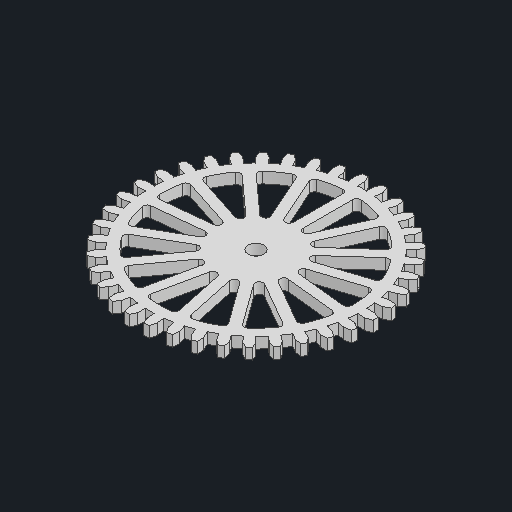
# Autodesk Inventor part: M3_38_holl_small
Saved by Autodesk Inventor 2027.1 (Build 311270010, 270A)
## iProperties
Created: 2024-04-01
Part Number: M3_38_holl_small
Material: 一般
Document SubType Name: モデリング
Designer: hibik
Density: 1 g/cm^3
Appearance: 既定
Sheet Metal Rule: Default
Author: hibik
Autodesk Inventor part; units mm, degrees
ref_plane "YZ Plane" through (0, 0, 0) normal (1, 0, 0) x (0, 1, 0)
ref_plane "XZ Plane" through (0, 0, 0) normal (0, 1, 0) x (-1, 0, 0)
ref_plane "XY Plane" through (0, 0, 0) normal (0, 0, 1) x (1, 0, 0)
sketch "スケッチ1" plane through (0, 0, 0) normal (0, 1, 0) x (-1, 0, 0)
  circle A0 centre (0, 0) radius 57 construction
  circle A1 centre (0, 0) radius 60 construction
  line L0 (60, 1.2454) -> (60, -1.2454)
  line L1 (60, 1.2454) -> (56.9513, 2.355)
  line L2 (60, -1.2454) -> (56.9513, -2.355)
  line L3 (84, 0) -> (-84, 0) projected
  circle A2 centre (0, 0) radius 53.25
  line L4 (56.9513, -2.355) -> (53.2045, -2.2001)
  line L5 (56.9513, 2.355) -> (53.2045, 2.2001)
  line L6 (55.787, 11.6968) -> (52.1168, 10.9272)
  line L7 (58.9767, 11.1041) -> (55.787, 11.6968)
  line L8 (58.9767, 11.1041) -> (59.3867, 8.6473)
  line L9 (59.3867, 8.6473) -> (56.5622, 7.051)
  line L10 (56.5622, 7.051) -> (52.841, 6.5871)
  line L11 (53.1009, 20.7195) -> (49.6074, 19.3563)
  line L12 (56.3447, 20.6599) -> (53.1009, 20.7195)
  line L13 (56.3447, 20.6599) -> (57.1534, 18.3041)
  line L14 (57.1534, 18.3041) -> (54.6302, 16.2647)
  line L15 (54.6302, 16.2647) -> (51.0361, 15.1946)
  line L16 (48.9663, 29.177) -> (45.7449, 27.2575)
  line L17 (52.1757, 29.6521) -> (48.9663, 29.177)
  line L18 (52.1757, 29.6521) -> (53.3612, 27.4616)
  line L19 (53.3612, 27.4616) -> (51.2081, 25.0347)
  line L20 (51.2081, 25.0347) -> (47.8391, 23.3877)
  line L21 (43.4961, 36.8387) -> (40.6345, 34.4151)
  line L22 (46.5835, 37.8355) -> (43.4961, 36.8387)
  line L23 (46.5835, 37.8355) -> (48.1134, 35.87)
  line L24 (48.1134, 35.87) -> (46.3891, 33.1218)
  line L25 (46.3891, 33.1218) -> (43.3372, 30.9427)
  line L26 (36.8395, 43.4955) -> (34.4158, 40.6339)
  line L27 (39.7206, 44.9869) -> (36.8395, 43.4955)
  line L28 (39.7206, 44.9869) -> (41.5531, 43.3)
  line L29 (41.5531, 43.3) -> (40.3047, 40.3055)
  line L30 (40.3047, 40.3055) -> (37.6531, 37.6538)
  line L31 (29.1779, 48.9658) -> (27.2583, 45.7444)
  line L32 (31.7743, 50.9111) -> (29.1779, 48.9658)
  line L33 (31.7743, 50.9111) -> (33.8595, 49.5488)
  line L34 (33.8595, 49.5488) -> (33.121, 46.3897)
  line L35 (33.121, 46.3897) -> (30.9419, 43.3377)
  line L36 (20.7204, 53.1005) -> (19.3573, 49.607)
  line L37 (22.9612, 55.4467) -> (20.7204, 53.1005)
  line L38 (22.9612, 55.4467) -> (25.2422, 54.4461)
  line L39 (25.2422, 54.4461) -> (25.0337, 51.2085)
  line L40 (25.0337, 51.2085) -> (23.3868, 47.8395)
  line L41 (11.6978, 55.7868) -> (10.9282, 52.1166)
  line L42 (13.5219, 58.4697) -> (11.6978, 55.7868)
  line L43 (13.5219, 58.4697) -> (15.9364, 57.8583)
  line L44 (15.9364, 57.8583) -> (16.2637, 54.6305)
  line L45 (16.2637, 54.6305) -> (15.1937, 51.0364)
  line L46 (2.356, 56.9513) -> (2.201, 53.2045)
  line L47 (3.7136, 59.8979) -> (2.356, 56.9513)
  line L48 (3.7136, 59.8979) -> (6.1959, 59.6922)
  line L49 (6.1959, 59.6922) -> (7.05, 56.5623)
  line L50 (7.05, 56.5623) -> (6.5861, 52.8411)
  line L51 (-7.05, 56.5623) -> (-6.5861, 52.8411)
  line L52 (-6.1959, 59.6922) -> (-7.05, 56.5623)
  line L53 (-6.1959, 59.6922) -> (-3.7136, 59.8979)
  line L54 (-3.7136, 59.8979) -> (-2.356, 56.9513)
  line L55 (-2.356, 56.9513) -> (-2.201, 53.2045)
  line L56 (-16.2637, 54.6305) -> (-15.1937, 51.0364)
  line L57 (-15.9364, 57.8583) -> (-16.2637, 54.6305)
  line L58 (-15.9364, 57.8583) -> (-13.5219, 58.4697)
  line L59 (-13.5219, 58.4697) -> (-11.6978, 55.7868)
  line L60 (-11.6978, 55.7868) -> (-10.9282, 52.1166)
  line L61 (-25.0337, 51.2085) -> (-23.3868, 47.8395)
  line L62 (-25.2422, 54.4461) -> (-25.0337, 51.2085)
  line L63 (-25.2422, 54.4461) -> (-22.9612, 55.4467)
  line L64 (-22.9612, 55.4467) -> (-20.7204, 53.1005)
  line L65 (-20.7204, 53.1005) -> (-19.3573, 49.607)
  line L66 (-33.121, 46.3897) -> (-30.9419, 43.3377)
  line L67 (-33.8595, 49.5488) -> (-33.121, 46.3897)
  line L68 (-33.8595, 49.5488) -> (-31.7743, 50.9111)
  line L69 (-31.7743, 50.9111) -> (-29.1779, 48.9658)
  line L70 (-29.1779, 48.9658) -> (-27.2583, 45.7444)
  line L71 (-40.3047, 40.3055) -> (-37.6531, 37.6538)
  line L72 (-41.5531, 43.3) -> (-40.3047, 40.3055)
  line L73 (-41.5531, 43.3) -> (-39.7206, 44.9869)
  line L74 (-39.7206, 44.9869) -> (-36.8395, 43.4955)
  line L75 (-36.8395, 43.4955) -> (-34.4158, 40.6339)
  line L76 (-46.3891, 33.1218) -> (-43.3372, 30.9427)
  line L77 (-48.1134, 35.87) -> (-46.3891, 33.1218)
  line L78 (-48.1134, 35.87) -> (-46.5835, 37.8355)
  line L79 (-46.5835, 37.8355) -> (-43.4961, 36.8387)
  line L80 (-43.4961, 36.8387) -> (-40.6345, 34.4151)
  line L81 (-51.2081, 25.0347) -> (-47.8391, 23.3877)
  line L82 (-53.3612, 27.4616) -> (-51.2081, 25.0347)
  line L83 (-53.3612, 27.4616) -> (-52.1757, 29.6521)
  line L84 (-52.1757, 29.6521) -> (-48.9663, 29.177)
  line L85 (-48.9663, 29.177) -> (-45.7449, 27.2575)
  line L86 (-54.6302, 16.2647) -> (-51.0361, 15.1946)
  line L87 (-57.1534, 18.3041) -> (-54.6302, 16.2647)
  line L88 (-57.1534, 18.3041) -> (-56.3447, 20.6599)
  line L89 (-56.3447, 20.6599) -> (-53.1009, 20.7195)
  line L90 (-53.1009, 20.7195) -> (-49.6074, 19.3563)
  line L91 (-56.5622, 7.051) -> (-52.841, 6.5871)
  line L92 (-59.3867, 8.6473) -> (-56.5622, 7.051)
  line L93 (-59.3867, 8.6473) -> (-58.9767, 11.1041)
  line L94 (-58.9767, 11.1041) -> (-55.787, 11.6968)
  line L95 (-55.787, 11.6968) -> (-52.1168, 10.9272)
  line L96 (-56.9513, -2.355) -> (-53.2045, -2.2001)
  line L97 (-60, -1.2454) -> (-56.9513, -2.355)
  line L98 (-60, -1.2454) -> (-60, 1.2454)
  line L99 (-60, 1.2454) -> (-56.9513, 2.355)
  line L100 (-56.9513, 2.355) -> (-53.2045, 2.2001)
  line L101 (-55.787, -11.6968) -> (-52.1168, -10.9272)
  line L102 (-58.9767, -11.1041) -> (-55.787, -11.6968)
  line L103 (-58.9767, -11.1041) -> (-59.3867, -8.6473)
  line L104 (-59.3867, -8.6473) -> (-56.5622, -7.051)
  line L105 (-56.5622, -7.051) -> (-52.841, -6.5871)
  line L106 (-53.1009, -20.7195) -> (-49.6074, -19.3563)
  line L107 (-56.3447, -20.6599) -> (-53.1009, -20.7195)
  line L108 (-56.3447, -20.6599) -> (-57.1534, -18.3041)
  line L109 (-57.1534, -18.3041) -> (-54.6302, -16.2647)
  line L110 (-54.6302, -16.2647) -> (-51.0361, -15.1946)
  line L111 (-48.9663, -29.177) -> (-45.7449, -27.2575)
  line L112 (-52.1757, -29.6521) -> (-48.9663, -29.177)
  line L113 (-52.1757, -29.6521) -> (-53.3612, -27.4616)
  line L114 (-53.3612, -27.4616) -> (-51.2081, -25.0347)
  line L115 (-51.2081, -25.0347) -> (-47.8391, -23.3877)
  line L116 (-43.4961, -36.8387) -> (-40.6345, -34.4151)
  line L117 (-46.5835, -37.8355) -> (-43.4961, -36.8387)
  line L118 (-46.5835, -37.8355) -> (-48.1134, -35.87)
  line L119 (-48.1134, -35.87) -> (-46.3891, -33.1218)
  line L120 (-46.3891, -33.1218) -> (-43.3372, -30.9427)
  line L121 (-36.8395, -43.4955) -> (-34.4158, -40.6339)
  line L122 (-39.7206, -44.9869) -> (-36.8395, -43.4955)
  line L123 (-39.7206, -44.9869) -> (-41.5531, -43.3)
  line L124 (-41.5531, -43.3) -> (-40.3047, -40.3055)
  line L125 (-40.3047, -40.3055) -> (-37.6531, -37.6538)
  line L126 (-29.1779, -48.9658) -> (-27.2583, -45.7444)
  line L127 (-31.7743, -50.9111) -> (-29.1779, -48.9658)
  line L128 (-31.7743, -50.9111) -> (-33.8595, -49.5488)
  line L129 (-33.8595, -49.5488) -> (-33.121, -46.3897)
  line L130 (-33.121, -46.3897) -> (-30.9419, -43.3377)
  line L131 (-20.7204, -53.1005) -> (-19.3573, -49.607)
  line L132 (-22.9612, -55.4467) -> (-20.7204, -53.1005)
  line L133 (-22.9612, -55.4467) -> (-25.2422, -54.4461)
  line L134 (-25.2422, -54.4461) -> (-25.0337, -51.2085)
  line L135 (-25.0337, -51.2085) -> (-23.3868, -47.8395)
  line L136 (-11.6978, -55.7868) -> (-10.9282, -52.1166)
  line L137 (-13.5219, -58.4697) -> (-11.6978, -55.7868)
  line L138 (-13.5219, -58.4697) -> (-15.9364, -57.8583)
  line L139 (-15.9364, -57.8583) -> (-16.2637, -54.6305)
  line L140 (-16.2637, -54.6305) -> (-15.1937, -51.0364)
  line L141 (-2.356, -56.9513) -> (-2.201, -53.2045)
  line L142 (-3.7136, -59.8979) -> (-2.356, -56.9513)
  line L143 (-3.7136, -59.8979) -> (-6.1959, -59.6922)
  line L144 (-6.1959, -59.6922) -> (-7.05, -56.5623)
  line L145 (-7.05, -56.5623) -> (-6.5861, -52.8411)
  line L146 (7.05, -56.5623) -> (6.5861, -52.8411)
  line L147 (6.1959, -59.6922) -> (7.05, -56.5623)
  line L148 (6.1959, -59.6922) -> (3.7136, -59.8979)
  line L149 (3.7136, -59.8979) -> (2.356, -56.9513)
  line L150 (2.356, -56.9513) -> (2.201, -53.2045)
  line L151 (16.2637, -54.6305) -> (15.1937, -51.0364)
  line L152 (15.9364, -57.8583) -> (16.2637, -54.6305)
  line L153 (15.9364, -57.8583) -> (13.5219, -58.4697)
  line L154 (13.5219, -58.4697) -> (11.6978, -55.7868)
  line L155 (11.6978, -55.7868) -> (10.9282, -52.1166)
  line L156 (25.0337, -51.2085) -> (23.3868, -47.8395)
  line L157 (25.2422, -54.4461) -> (25.0337, -51.2085)
  line L158 (25.2422, -54.4461) -> (22.9612, -55.4467)
  line L159 (22.9612, -55.4467) -> (20.7204, -53.1005)
  line L160 (20.7204, -53.1005) -> (19.3573, -49.607)
  line L161 (33.121, -46.3897) -> (30.9419, -43.3377)
  line L162 (33.8595, -49.5488) -> (33.121, -46.3897)
  line L163 (33.8595, -49.5488) -> (31.7743, -50.9111)
  line L164 (31.7743, -50.9111) -> (29.1779, -48.9658)
  line L165 (29.1779, -48.9658) -> (27.2583, -45.7444)
  line L166 (40.3047, -40.3055) -> (37.6531, -37.6538)
  line L167 (41.5531, -43.3) -> (40.3047, -40.3055)
  line L168 (41.5531, -43.3) -> (39.7206, -44.9869)
  line L169 (39.7206, -44.9869) -> (36.8395, -43.4955)
  line L170 (36.8395, -43.4955) -> (34.4158, -40.6339)
  line L171 (46.3891, -33.1218) -> (43.3372, -30.9427)
  line L172 (48.1134, -35.87) -> (46.3891, -33.1218)
  line L173 (48.1134, -35.87) -> (46.5835, -37.8355)
  line L174 (46.5835, -37.8355) -> (43.4961, -36.8387)
  line L175 (43.4961, -36.8387) -> (40.6345, -34.4151)
  line L176 (51.2081, -25.0347) -> (47.8391, -23.3877)
  line L177 (53.3612, -27.4616) -> (51.2081, -25.0347)
  line L178 (53.3612, -27.4616) -> (52.1757, -29.6521)
  line L179 (52.1757, -29.6521) -> (48.9663, -29.177)
  line L180 (48.9663, -29.177) -> (45.7449, -27.2575)
  line L181 (54.6302, -16.2647) -> (51.0361, -15.1946)
  line L182 (57.1534, -18.3041) -> (54.6302, -16.2647)
  line L183 (57.1534, -18.3041) -> (56.3447, -20.6599)
  line L184 (56.3447, -20.6599) -> (53.1009, -20.7195)
  line L185 (53.1009, -20.7195) -> (49.6074, -19.3563)
  line L186 (56.5622, -7.051) -> (52.841, -6.5871)
  line L187 (59.3867, -8.6473) -> (56.5622, -7.051)
  line L188 (59.3867, -8.6473) -> (58.9767, -11.1041)
  line L189 (58.9767, -11.1041) -> (55.787, -11.6968)
  line L190 (55.787, -11.6968) -> (52.1168, -10.9272)
  circle A3 centre (0, 0) radius 7
  point P0 (60, 0)
  point P1 (59.1817, 9.8757)
  point P2 (56.749, 19.482)
  point P3 (52.7684, 28.5568)
  point P4 (47.3484, 36.8528)
  point P5 (40.6369, 44.1434)
  point P6 (32.8169, 50.23)
  point P7 (24.1017, 54.9464)
  point P8 (14.7291, 58.164)
  point P9 (4.9548, 59.7951)
  point P10 (-4.9548, 59.7951)
  point P11 (-14.7291, 58.164)
  point P12 (-24.1017, 54.9464)
  point P13 (-32.8169, 50.23)
  point P14 (-40.6369, 44.1434)
  point P15 (-47.3484, 36.8528)
  point P16 (-52.7684, 28.5568)
  point P17 (-56.749, 19.482)
  point P18 (-59.1817, 9.8757)
  point P19 (-60, 0)
  point P20 (-59.1817, -9.8757)
  point P21 (-56.749, -19.482)
  point P22 (-52.7684, -28.5568)
  point P23 (-47.3484, -36.8528)
  point P24 (-40.6369, -44.1434)
  point P25 (-32.8169, -50.23)
  point P26 (-24.1017, -54.9464)
  point P27 (-14.7291, -58.164)
  point P28 (-4.9548, -59.7951)
  point P29 (4.9548, -59.7951)
  point P30 (14.7291, -58.164)
  point P31 (24.1017, -54.9464)
  point P32 (32.8169, -50.23)
  point P33 (40.6369, -44.1434)
  point P34 (47.3484, -36.8528)
  point P35 (52.7684, -28.5568)
  point P36 (56.749, -19.482)
  point P37 (59.1817, -9.8757)
  point P38 (-43.3372, -30.9427)
  point P39 (-40.6345, -34.4151)
  point P40 (-37.6531, -37.6538)
  point P41 (-34.4158, -40.6339)
  point P42 (-30.9419, -43.3377)
  point P43 (-19.3573, -49.607)
  point P44 (-15.1937, -51.0364)
  point P45 (-10.9282, -52.1166)
  point P46 (-6.5861, -52.8411)
  point P47 (-2.201, -53.2045)
  point P48 (2.201, -53.2045)
  point P49 (10.9282, -52.1166)
  point P50 (15.1937, -51.0364)
  point P51 (19.3573, -49.607)
  point P52 (23.3868, -47.8395)
  point P53 (27.2583, -45.7444)
  point P54 (30.9419, -43.3377)
  point P55 (34.4158, -40.6339)
  point P56 (37.6531, -37.6538)
  point P57 (40.6345, -34.4151)
  point P58 (43.3372, -30.9427)
  point P59 (45.7449, -27.2575)
  point P60 (47.8391, -23.3877)
  point P61 (49.6074, -19.3563)
  point P62 (51.0361, -15.1946)
  point P63 (52.1168, -10.9272)
  point P64 (52.841, -6.5871)
  point P65 (52.841, 6.5871)
  point P66 (52.1168, 10.9272)
  point P67 (49.6074, 19.3563)
  point P68 (45.7449, 27.2575)
  point P69 (40.6345, 34.4151)
  point P70 (37.6531, 37.6538)
  point P71 (34.4158, 40.6339)
  point P72 (27.2583, 45.7444)
  point P73 (19.3573, 49.607)
  point P74 (15.1937, 51.0364)
  point P75 (10.9282, 52.1166)
  point P76 (6.5861, 52.8411)
  point P77 (2.201, 53.2045)
  point P78 (-2.201, 53.2045)
  point P79 (-6.5861, 52.8411)
  point P80 (-10.9282, 52.1166)
  point P81 (-15.1937, 51.0364)
  point P82 (-19.3573, 49.607)
  point P83 (-23.3868, 47.8395)
  point P84 (-27.2583, 45.7444)
  point P85 (-30.9419, 43.3377)
  point P86 (-34.4158, 40.6339)
  point P87 (-37.6531, 37.6538)
  point P88 (-43.3372, 30.9427)
  point P89 (-45.7449, 27.2575)
  point P90 (-47.8391, 23.3877)
  point P91 (-49.6074, 19.3563)
  point P92 (-51.0361, 15.1946)
  point P93 (-52.1168, 10.9272)
  point P94 (-52.841, -6.5871)
  point P95 (-52.1168, -10.9272)
  point P96 (-51.0361, -15.1946)
  point P97 (-49.6074, -19.3563)
  point P98 (-47.8391, -23.3877)
  dimension "d5" = 106.5
  dimension "d0" = 114
  dimension "d1" = 120
  dimension "d3" = 20
  dimension "d4" = 20
  dimension "d14" = 4.71
  dimension "d18" = 360
  dimension "d24" = 14
  constraints: 380 end point, 77 point on line, 6 coincident, 3 centre point, 2 point on circle, 1 midpoint, 1 tangent, 1 vertical, 496 other
  measures "d0" diameter of A0
  measures "d1" diameter of A1
  measures "d3" angle of L3 L1
  measures "d4" angle of L3 L2
  measures "d14" distance of L2.end L1.end
  measures "d24" diameter of A3
extrude "押し出し1" add sketch "スケッチ1" along normal blind 5.5 contours L0 L3 A2 L5 L1 | L0 L2 L4 A2 L3 | A2 L3 A3 | L3 A3 A2 | A2 L6 L7 L8 L9 L10 | L186 L187 L188 L189 L190 A2 | A2 L96 L97 L98 L3 | L3 L98 L99 L100 A2 | A2 L11 L12 L13 L14 L15 | L181 L182 L183 L184 L185 A2 | L91 L92 L93 L94 L95 A2 | A2 L101 L102 L103 L104 L105 | A2 L16 L17 L18 L19 L20 | L176 L177 L178 L179 L180 A2 | L86 L87 L88 L89 L90 A2 | A2 L106 L107 L108 L109 L110 | A2 L21 L22 L23 L24 L25 | L171 L172 L173 L174 L175 A2 | L81 L82 L83 L84 L85 A2 | A2 L111 L112 L113 L114 L115 | A2 L26 L27 L28 L29 L30 | L166 L167 L168 L169 L170 A2 | L76 L77 L78 L79 L80 A2 | A2 L116 L117 L118 L119 L120 | A2 L31 L32 L33 L34 L35 | L161 L162 L163 L164 L165 A2 | L71 L72 L73 L74 L75 A2 | A2 L121 L122 L123 L124 L125 | A2 L36 L37 L38 L39 L40 | L156 L157 L158 L159 L160 A2 | L66 L67 L68 L69 L70 A2 | A2 L126 L127 L128 L129 L130 | A2 L41 L42 L43 L44 L45 | L151 L152 L153 L154 L155 A2 | L61 L62 L63 L64 L65 A2 | A2 L131 L132 L133 L134 L135 | A2 L46 L47 L48 L49 L50 | L146 L147 L148 L149 L150 A2 | L56 L57 L58 L59 L60 A2 | A2 L136 L137 L138 L139 L140 | A2 L51 L52 L53 L54 L55 | L141 L142 L143 L144 L145 A2
sketch "スケッチ2" plane through (0, 5.5, 0) normal (0, 1, 0) x (1, 0, 0)
  circle A0 centre (0, 0) radius 7 projected
  arc A1 (-15.1937, 51.0364) -> (-19.3573, 49.607) centre (0, 0) ccw projected
  circle A2 centre (0, 0) radius 12
  circle A3 centre (0, 0) radius 48.25
  line L0 (-2.5, 48.25) -> (2.5, 48.25) construction
  line L1 (2.5, 48.25) -> (2.5, 0)
  line L2 (2.5, 0) -> (-2.5, 0)
  line L3 (-2.5, 0) -> (-2.5, 48.25)
  point P0 (-2.5, 11.7367)
  point P1 (-2.5, 48.1852)
  point P2 (2.5, 48.1852)
  point P3 (2.5, 11.7367)
  dimension "d25" = 5
  dimension "d26" = 5
  dimension "d27" = 5
  constraints: 8 end point, 3 coincident, 2 centre point, 2 parallel, 1 horizontal, 1 midpoint, 1 perpendicular, 1 tangent
  measures "d25" radial gap between concentric circles of A3 A1
  measures "d26" radial gap between concentric circles of A2 A0
  measures "d27" distance of L0.start L0.end
extrude "押し出し2" cut sketch "スケッチ2" against normal through all contours L1 A3 L3 A2 | A2 L3 A3 L1
sketch "スケッチ4" plane through (0, 5.5, 0) normal (0, 1, 0) x (1, 0, 0)
  line L0 (-2.5, 48.1852) -> (2.5, 48.1852) construction
  line L1 (2.5, 48.1852) -> (2.5, 0)
  line L2 (2.5, 0) -> (-2.5, 0)
  line L3 (-2.5, 0) -> (-2.5, 48.1852)
  circle A0 centre (0, 0) radius 48.25 projected
  circle A1 centre (0, 0) radius 12 projected
  point P0 (-2.5, 11.7367)
  point P1 (2.5, 11.7367)
  point P2 (-2.5, 48.1852)
  dimension "d32" = 5
  constraints: 8 end point, 2 parallel, 1 coincident, 1 horizontal, 1 midpoint, 1 perpendicular, 2 other
  measures "d32" distance of L1.end L2.end
extrude "押し出し4" add sketch "スケッチ4" against normal up to surface (5.5 mm away) contours L1 A1 L3 A0 picked at (-0.2779, 24.0614)
pattern_circular "円形状パターン1" count 15 over 360 about axis through (0, -10, 0) along (0, 1, 0) of "押し出し4"
fillet "フィレット1" radius 2 3 edges at (7.5729, 2.75, 47.652) (-7.5729, 2.75, 47.652) (0, 2.75, 12.0243)
pattern_circular "円形状パターン2" count 15 over 360 about axis through (0, -10, 0) along (0, 1, 0) of "フィレット1"
sketch "スケッチ5" plane through (0, 5.5, 0) normal (0, 1, 0) x (1, 0, 0)
  arc A0 (32.5453, 35.6211) -> (23.8207, 41.96) centre (0, 0) ccw projected
  arc A1 (32.5345, 32.6583) -> (32.5453, 35.6211) centre (31.1963, 34.1446) ccw projected
  line L0 (32.5345, 32.6583) -> (14.0602, 16.0239) projected
  arc A2 (10.8948, 18.3237) -> (14.0602, 16.0239) centre (12.7219, 17.5102) ccw projected
  line L1 (10.8948, 18.3237) -> (21.0062, 41.0342) projected
  arc A3 (23.8207, 41.96) -> (21.0062, 41.0342) centre (22.8333, 40.2207) ccw projected
  line L2 (16.4385, 43.0679) -> (6.3271, 20.3574) projected
  arc A4 (2.5, 21.1708) -> (6.3271, 20.3574) centre (4.5, 21.1708) ccw projected
  line L3 (2.5, 21.1708) -> (2.5, 46.0306) projected
  arc A5 (4.6946, 48.0211) -> (2.5, 46.0306) centre (4.5, 46.0306) ccw projected
  arc A6 (15.2432, 45.7789) -> (4.6946, 48.0211) centre (0, 0) ccw projected
  arc A7 (16.4385, 43.0679) -> (15.2432, 45.7789) centre (14.6114, 43.8813) ccw projected
  line L4 (-6.3271, 20.3574) -> (-16.4385, 43.0679) projected
  arc A8 (-15.2432, 45.7789) -> (-16.4385, 43.0679) centre (-14.6114, 43.8813) ccw projected
  arc A9 (-4.6946, 48.0211) -> (-15.2432, 45.7789) centre (0, 0) ccw projected
  arc A10 (-2.5, 46.0306) -> (-4.6946, 48.0211) centre (-4.5, 46.0306) ccw projected
  line L5 (-2.5, 46.0306) -> (-2.5, 21.1708) projected
  arc A11 (-6.3271, 20.3574) -> (-2.5, 21.1708) centre (-4.5, 21.1708) ccw projected
  line L6 (-21.0062, 41.0342) -> (-10.8948, 18.3237) projected
  arc A12 (-14.0602, 16.0239) -> (-10.8948, 18.3237) centre (-12.7219, 17.5102) ccw projected
  line L7 (-14.0602, 16.0239) -> (-32.5345, 32.6583) projected
  arc A13 (-32.5453, 35.6211) -> (-32.5345, 32.6583) centre (-31.1963, 34.1446) ccw projected
  arc A14 (-23.8207, 41.96) -> (-32.5453, 35.6211) centre (0, 0) ccw projected
  arc A15 (-21.0062, 41.0342) -> (-23.8207, 41.96) centre (-22.8333, 40.2207) ccw projected
  line L8 (-35.8802, 28.9426) -> (-17.4058, 12.3082) projected
  arc A16 (-19.3621, 8.9198) -> (-17.4058, 12.3082) centre (-18.7441, 10.8219) ccw projected
  line L9 (-19.3621, 8.9198) -> (-43.0051, 16.6019) projected
  arc A17 (-44.22, 19.3042) -> (-43.0051, 16.6019) centre (-42.3871, 18.504) ccw projected
  arc A18 (-38.8279, 28.6436) -> (-44.22, 19.3042) centre (0, 0) ccw projected
  arc A19 (-35.8802, 28.9426) -> (-38.8279, 28.6436) centre (-37.2185, 27.4563) ccw projected
  line L10 (-44.5502, 11.8466) -> (-20.9072, 4.1645) projected
  arc A20 (-21.3162, 0.2733) -> (-20.9072, 4.1645) centre (-21.5252, 2.2624) ccw projected
  line L11 (-21.3162, 0.2733) -> (-46.0397, -2.3252) projected
  arc A21 (-48.2487, -0.3507) -> (-46.0397, -2.3252) centre (-46.2488, -0.3362) ccw projected
  arc A22 (-47.1215, 10.3745) -> (-48.2487, -0.3507) centre (0, 0) ccw projected
  arc A23 (-44.5502, 11.8466) -> (-47.1215, 10.3745) centre (-45.1682, 9.9445) ccw projected
  line L12 (-45.5171, -7.2978) -> (-20.7935, -4.6993) projected
  arc A24 (-19.5845, -8.4204) -> (-20.7935, -4.6993) centre (-20.5845, -6.6883) ccw projected
  line L13 (-19.5845, -8.4204) -> (-41.1136, -20.8502) projected
  arc A25 (-43.9348, -19.9449) -> (-41.1136, -20.8502) centre (-42.1136, -19.1182) ccw projected
  arc A26 (-47.2673, -9.6884) -> (-43.9348, -19.9449) centre (0, 0) ccw projected
  arc A27 (-45.5171, -7.2978) -> (-47.2673, -9.6884) centre (-45.308, -9.2869) ccw projected
  line L14 (-38.6136, -25.1803) -> (-17.0845, -12.7505) projected
  arc A28 (-14.4664, -15.6581) -> (-17.0845, -12.7505) centre (-16.0845, -14.4825) ccw projected
  line L15 (-14.4664, -15.6581) -> (-29.0786, -35.77) projected
  arc A29 (-32.0241, -36.0904) -> (-29.0786, -35.77) centre (-30.6967, -34.5945) ccw projected
  arc A30 (-39.2402, -28.0762) -> (-32.0241, -36.0904) centre (0, 0) ccw projected
  arc A31 (-38.6136, -25.1803) -> (-39.2402, -28.0762) centre (-37.6136, -26.9124) ccw projected
  line L16 (-25.0335, -38.709) -> (-10.4214, -18.597) projected
  arc A32 (-6.847, -20.1884) -> (-10.4214, -18.597) centre (-8.8033, -19.7726) ccw projected
  line L17 (-6.847, -20.1884) -> (-12.0157, -44.5049) projected
  arc A33 (-14.5761, -45.9956) -> (-12.0157, -44.5049) centre (-13.972, -44.0891) ccw projected
  arc A34 (-24.4281, -41.6093) -> (-14.5761, -45.9956) centre (0, 0) ccw projected
  arc A35 (-25.0335, -38.709) -> (-24.4281, -41.6093) centre (-23.4155, -39.8845) ccw projected
  line L18 (-7.1249, -45.5445) -> (-1.9563, -21.228) projected
  arc A36 (1.9563, -21.228) -> (-1.9563, -21.228) centre (0, -21.6438) ccw projected
  line L19 (1.9563, -21.228) -> (7.1249, -45.5445) projected
  arc A37 (5.3921, -47.9478) -> (7.1249, -45.5445) centre (5.1686, -45.9603) ccw projected
  arc A38 (-5.3921, -47.9478) -> (5.3921, -47.9478) centre (0, 0) ccw projected
  arc A39 (-7.1249, -45.5445) -> (-5.3921, -47.9478) centre (-5.1686, -45.9603) ccw projected
  line L20 (12.0157, -44.5049) -> (6.847, -20.1884) projected
  arc A40 (10.4214, -18.597) -> (6.847, -20.1884) centre (8.8033, -19.7726) ccw projected
  line L21 (10.4214, -18.597) -> (25.0335, -38.709) projected
  arc A41 (24.4281, -41.6093) -> (25.0335, -38.709) centre (23.4155, -39.8845) ccw projected
  arc A42 (14.5761, -45.9956) -> (24.4281, -41.6093) centre (0, 0) ccw projected
  arc A43 (12.0157, -44.5049) -> (14.5761, -45.9956) centre (13.972, -44.0891) ccw projected
  line L22 (29.0786, -35.77) -> (14.4664, -15.6581) projected
  arc A44 (17.0845, -12.7505) -> (14.4664, -15.6581) centre (16.0845, -14.4825) ccw projected
  line L23 (17.0845, -12.7505) -> (38.6136, -25.1803) projected
  arc A45 (39.2402, -28.0762) -> (38.6136, -25.1803) centre (37.6136, -26.9124) ccw projected
  arc A46 (32.0241, -36.0904) -> (39.2402, -28.0762) centre (0, 0) ccw projected
  arc A47 (29.0786, -35.77) -> (32.0241, -36.0904) centre (30.6967, -34.5945) ccw projected
  line L24 (41.1136, -20.8502) -> (19.5845, -8.4204) projected
  arc A48 (20.7935, -4.6993) -> (19.5845, -8.4204) centre (20.5845, -6.6883) ccw projected
  line L25 (20.7935, -4.6993) -> (45.5171, -7.2978) projected
  arc A49 (47.2673, -9.6884) -> (45.5171, -7.2978) centre (45.308, -9.2869) ccw projected
  arc A50 (43.9348, -19.9449) -> (47.2673, -9.6884) centre (0, 0) ccw projected
  arc A51 (41.1136, -20.8502) -> (43.9348, -19.9449) centre (42.1136, -19.1182) ccw projected
  line L26 (46.0397, -2.3252) -> (21.3162, 0.2733) projected
  arc A52 (20.9072, 4.1645) -> (21.3162, 0.2733) centre (21.5252, 2.2624) ccw projected
  line L27 (20.9072, 4.1645) -> (44.5502, 11.8466) projected
  arc A53 (47.1215, 10.3745) -> (44.5502, 11.8466) centre (45.1682, 9.9445) ccw projected
  arc A54 (48.2487, -0.3507) -> (47.1215, 10.3745) centre (0, 0) ccw projected
  arc A55 (46.0397, -2.3252) -> (48.2487, -0.3507) centre (46.2488, -0.3362) ccw projected
  line L28 (43.0051, 16.6019) -> (19.3621, 8.9198) projected
  arc A56 (17.4058, 12.3082) -> (19.3621, 8.9198) centre (18.7441, 10.8219) ccw projected
  line L29 (17.4058, 12.3082) -> (35.8802, 28.9426) projected
  arc A57 (38.8279, 28.6436) -> (35.8802, 28.9426) centre (37.2185, 27.4563) ccw projected
  arc A58 (44.22, 19.3042) -> (38.8279, 28.6436) centre (0, 0) ccw projected
  arc A59 (43.0051, 16.6019) -> (44.22, 19.3042) centre (42.3871, 18.504) ccw projected
  line L30 (-52.841, -6.5871) -> (-56.5622, -7.051) projected
  line L31 (-56.5622, -7.051) -> (-59.3867, -8.6473) projected
  line L32 (-59.3867, -8.6473) -> (-58.9767, -11.1041) projected
  line L33 (-58.9767, -11.1041) -> (-55.787, -11.6968) projected
  line L34 (-55.787, -11.6968) -> (-52.1168, -10.9272) projected
  arc A60 (-52.1168, -10.9272) -> (-51.0361, -15.1946) centre (0, 0) ccw projected
  line L35 (-51.0361, -15.1946) -> (-54.6302, -16.2647) projected
  line L36 (-54.6302, -16.2647) -> (-57.1534, -18.3041) projected
  line L37 (-57.1534, -18.3041) -> (-56.3447, -20.6599) projected
  line L38 (-56.3447, -20.6599) -> (-53.1009, -20.7195) projected
  line L39 (-53.1009, -20.7195) -> (-49.6074, -19.3563) projected
  arc A61 (-49.6074, -19.3563) -> (-47.8391, -23.3877) centre (0, 0) ccw projected
  line L40 (-47.8391, -23.3877) -> (-51.2081, -25.0347) projected
  line L41 (-51.2081, -25.0347) -> (-53.3612, -27.4616) projected
  line L42 (-53.3612, -27.4616) -> (-52.1757, -29.6521) projected
  line L43 (-52.1757, -29.6521) -> (-48.9663, -29.177) projected
  line L44 (-48.9663, -29.177) -> (-45.7449, -27.2575) projected
  arc A62 (-45.7449, -27.2575) -> (-43.3372, -30.9427) centre (0, 0) ccw projected
  line L45 (-43.3372, -30.9427) -> (-46.3891, -33.1218) projected
  line L46 (-46.3891, -33.1218) -> (-48.1134, -35.87) projected
  line L47 (-48.1134, -35.87) -> (-46.5835, -37.8355) projected
  line L48 (-46.5835, -37.8355) -> (-43.4961, -36.8387) projected
  line L49 (-43.4961, -36.8387) -> (-40.6345, -34.4151) projected
  arc A63 (-40.6345, -34.4151) -> (-37.6531, -37.6538) centre (0, 0) ccw projected
  line L50 (-37.6531, -37.6538) -> (-40.3047, -40.3055) projected
  line L51 (-40.3047, -40.3055) -> (-41.5531, -43.3) projected
  line L52 (-41.5531, -43.3) -> (-39.7206, -44.9869) projected
  line L53 (-39.7206, -44.9869) -> (-36.8395, -43.4955) projected
  line L54 (-36.8395, -43.4955) -> (-34.4158, -40.6339) projected
  arc A64 (-34.4158, -40.6339) -> (-30.9419, -43.3377) centre (0, 0) ccw projected
  line L55 (-30.9419, -43.3377) -> (-33.121, -46.3897) projected
  line L56 (-33.121, -46.3897) -> (-33.8595, -49.5488) projected
  line L57 (-33.8595, -49.5488) -> (-31.7743, -50.9111) projected
  line L58 (-31.7743, -50.9111) -> (-29.1779, -48.9658) projected
  line L59 (-29.1779, -48.9658) -> (-27.2583, -45.7444) projected
  arc A65 (-27.2583, -45.7444) -> (-23.3868, -47.8395) centre (0, 0) ccw projected
  line L60 (-23.3868, -47.8395) -> (-25.0337, -51.2085) projected
  line L61 (-25.0337, -51.2085) -> (-25.2422, -54.4461) projected
  line L62 (-25.2422, -54.4461) -> (-22.9612, -55.4467) projected
  line L63 (-22.9612, -55.4467) -> (-20.7204, -53.1005) projected
  line L64 (-20.7204, -53.1005) -> (-19.3573, -49.607) projected
  arc A66 (-19.3573, -49.607) -> (-15.1937, -51.0364) centre (0, 0) ccw projected
  line L65 (-15.1937, -51.0364) -> (-16.2637, -54.6305) projected
  line L66 (-16.2637, -54.6305) -> (-15.9364, -57.8583) projected
  line L67 (-15.9364, -57.8583) -> (-13.5219, -58.4697) projected
  line L68 (-13.5219, -58.4697) -> (-11.6978, -55.7868) projected
  line L69 (-11.6978, -55.7868) -> (-10.9282, -52.1166) projected
  arc A67 (-10.9282, -52.1166) -> (-6.5861, -52.8411) centre (0, 0) ccw projected
  line L70 (-6.5861, -52.8411) -> (-7.05, -56.5623) projected
  line L71 (-7.05, -56.5623) -> (-6.1959, -59.6922) projected
  line L72 (-6.1959, -59.6922) -> (-3.7136, -59.8979) projected
  line L73 (-3.7136, -59.8979) -> (-2.356, -56.9513) projected
  line L74 (-2.356, -56.9513) -> (-2.201, -53.2045) projected
  arc A68 (-2.201, -53.2045) -> (2.201, -53.2045) centre (0, 0) ccw projected
  line L75 (2.201, -53.2045) -> (2.356, -56.9513) projected
  line L76 (2.356, -56.9513) -> (3.7136, -59.8979) projected
  line L77 (3.7136, -59.8979) -> (6.1959, -59.6922) projected
  line L78 (6.1959, -59.6922) -> (7.05, -56.5623) projected
  line L79 (7.05, -56.5623) -> (6.5861, -52.8411) projected
  arc A69 (6.5861, -52.8411) -> (10.9282, -52.1166) centre (0, 0) ccw projected
  line L80 (10.9282, -52.1166) -> (11.6978, -55.7868) projected
  line L81 (11.6978, -55.7868) -> (13.5219, -58.4697) projected
  line L82 (13.5219, -58.4697) -> (15.9364, -57.8583) projected
  line L83 (15.9364, -57.8583) -> (16.2637, -54.6305) projected
  line L84 (16.2637, -54.6305) -> (15.1937, -51.0364) projected
  arc A70 (15.1937, -51.0364) -> (19.3573, -49.607) centre (0, 0) ccw projected
  line L85 (19.3573, -49.607) -> (20.7204, -53.1005) projected
  line L86 (20.7204, -53.1005) -> (22.9612, -55.4467) projected
  line L87 (22.9612, -55.4467) -> (25.2422, -54.4461) projected
  line L88 (25.2422, -54.4461) -> (25.0337, -51.2085) projected
  line L89 (25.0337, -51.2085) -> (23.3868, -47.8395) projected
  arc A71 (23.3868, -47.8395) -> (27.2583, -45.7444) centre (0, 0) ccw projected
  line L90 (27.2583, -45.7444) -> (29.1779, -48.9658) projected
  line L91 (29.1779, -48.9658) -> (31.7743, -50.9111) projected
  line L92 (31.7743, -50.9111) -> (33.8595, -49.5488) projected
  line L93 (33.8595, -49.5488) -> (33.121, -46.3897) projected
  line L94 (33.121, -46.3897) -> (30.9419, -43.3377) projected
  arc A72 (30.9419, -43.3377) -> (34.4158, -40.6339) centre (0, 0) ccw projected
  line L95 (34.4158, -40.6339) -> (36.8395, -43.4955) projected
  line L96 (36.8395, -43.4955) -> (39.7206, -44.9869) projected
  line L97 (39.7206, -44.9869) -> (41.5531, -43.3) projected
  line L98 (41.5531, -43.3) -> (40.3047, -40.3055) projected
  line L99 (40.3047, -40.3055) -> (37.6531, -37.6538) projected
  arc A73 (37.6531, -37.6538) -> (40.6345, -34.4151) centre (0, 0) ccw projected
  line L100 (40.6345, -34.4151) -> (43.4961, -36.8387) projected
  line L101 (43.4961, -36.8387) -> (46.5835, -37.8355) projected
  line L102 (46.5835, -37.8355) -> (48.1134, -35.87) projected
  line L103 (48.1134, -35.87) -> (46.3891, -33.1218) projected
  line L104 (46.3891, -33.1218) -> (43.3372, -30.9427) projected
  arc A74 (43.3372, -30.9427) -> (45.7449, -27.2575) centre (0, 0) ccw projected
  line L105 (45.7449, -27.2575) -> (48.9663, -29.177) projected
  line L106 (48.9663, -29.177) -> (52.1757, -29.6521) projected
  line L107 (52.1757, -29.6521) -> (53.3612, -27.4616) projected
  line L108 (53.3612, -27.4616) -> (51.2081, -25.0347) projected
  line L109 (51.2081, -25.0347) -> (47.8391, -23.3877) projected
  arc A75 (47.8391, -23.3877) -> (49.6074, -19.3563) centre (0, 0) ccw projected
  line L110 (49.6074, -19.3563) -> (53.1009, -20.7195) projected
  line L111 (53.1009, -20.7195) -> (56.3447, -20.6599) projected
  line L112 (56.3447, -20.6599) -> (57.1534, -18.3041) projected
  line L113 (57.1534, -18.3041) -> (54.6302, -16.2647) projected
  line L114 (54.6302, -16.2647) -> (51.0361, -15.1946) projected
  arc A76 (51.0361, -15.1946) -> (52.1168, -10.9272) centre (0, 0) ccw projected
  line L115 (52.1168, -10.9272) -> (55.787, -11.6968) projected
  line L116 (55.787, -11.6968) -> (58.9767, -11.1041) projected
  line L117 (58.9767, -11.1041) -> (59.3867, -8.6473) projected
  line L118 (59.3867, -8.6473) -> (56.5622, -7.051) projected
  line L119 (56.5622, -7.051) -> (52.841, -6.5871) projected
  arc A77 (52.841, -6.5871) -> (53.2045, -2.2001) centre (0, 0) ccw projected
  line L120 (53.2045, -2.2001) -> (56.9513, -2.355) projected
  line L121 (56.9513, -2.355) -> (60, -1.2454) projected
  line L122 (60, -1.2454) -> (60, 1.2454) projected
  line L123 (60, 1.2454) -> (56.9513, 2.355) projected
  line L124 (56.9513, 2.355) -> (53.2045, 2.2001) projected
  arc A78 (53.2045, 2.2001) -> (52.841, 6.5871) centre (0, 0) ccw projected
  line L125 (52.841, 6.5871) -> (56.5622, 7.051) projected
  line L126 (56.5622, 7.051) -> (59.3867, 8.6473) projected
  line L127 (59.3867, 8.6473) -> (58.9767, 11.1041) projected
  line L128 (58.9767, 11.1041) -> (55.787, 11.6968) projected
  line L129 (55.787, 11.6968) -> (52.1168, 10.9272) projected
  arc A79 (52.1168, 10.9272) -> (51.0361, 15.1946) centre (0, 0) ccw projected
  line L130 (51.0361, 15.1946) -> (54.6302, 16.2647) projected
  line L131 (54.6302, 16.2647) -> (57.1534, 18.3041) projected
  line L132 (57.1534, 18.3041) -> (56.3447, 20.6599) projected
  line L133 (56.3447, 20.6599) -> (53.1009, 20.7195) projected
  line L134 (53.1009, 20.7195) -> (49.6074, 19.3563) projected
  arc A80 (49.6074, 19.3563) -> (47.8391, 23.3877) centre (0, 0) ccw projected
  line L135 (47.8391, 23.3877) -> (51.2081, 25.0347) projected
  line L136 (51.2081, 25.0347) -> (53.3612, 27.4616) projected
  line L137 (53.3612, 27.4616) -> (52.1757, 29.6521) projected
  line L138 (52.1757, 29.6521) -> (48.9663, 29.177) projected
  line L139 (48.9663, 29.177) -> (45.7449, 27.2575) projected
  arc A81 (45.7449, 27.2575) -> (43.3372, 30.9427) centre (0, 0) ccw projected
  line L140 (43.3372, 30.9427) -> (46.3891, 33.1218) projected
  line L141 (46.3891, 33.1218) -> (48.1134, 35.87) projected
  line L142 (48.1134, 35.87) -> (46.5835, 37.8355) projected
  line L143 (46.5835, 37.8355) -> (43.4961, 36.8387) projected
  line L144 (43.4961, 36.8387) -> (40.6345, 34.4151) projected
  arc A82 (40.6345, 34.4151) -> (37.6531, 37.6538) centre (0, 0) ccw projected
  line L145 (37.6531, 37.6538) -> (40.3047, 40.3055) projected
  line L146 (40.3047, 40.3055) -> (41.5531, 43.3) projected
  line L147 (41.5531, 43.3) -> (39.7206, 44.9869) projected
  line L148 (39.7206, 44.9869) -> (36.8395, 43.4955) projected
  line L149 (36.8395, 43.4955) -> (34.4158, 40.6339) projected
  arc A83 (34.4158, 40.6339) -> (30.9419, 43.3377) centre (0, 0) ccw projected
  line L150 (30.9419, 43.3377) -> (33.121, 46.3897) projected
  line L151 (33.121, 46.3897) -> (33.8595, 49.5488) projected
  line L152 (33.8595, 49.5488) -> (31.7743, 50.9111) projected
  line L153 (31.7743, 50.9111) -> (29.1779, 48.9658) projected
  line L154 (29.1779, 48.9658) -> (27.2583, 45.7444) projected
  arc A84 (27.2583, 45.7444) -> (23.3868, 47.8395) centre (0, 0) ccw projected
  line L155 (23.3868, 47.8395) -> (25.0337, 51.2085) projected
  line L156 (25.0337, 51.2085) -> (25.2422, 54.4461) projected
  line L157 (25.2422, 54.4461) -> (22.9612, 55.4467) projected
  line L158 (22.9612, 55.4467) -> (20.7204, 53.1005) projected
  line L159 (20.7204, 53.1005) -> (19.3573, 49.607) projected
  arc A85 (19.3573, 49.607) -> (15.1937, 51.0364) centre (0, 0) ccw projected
  line L160 (15.1937, 51.0364) -> (16.2637, 54.6305) projected
  line L161 (16.2637, 54.6305) -> (15.9364, 57.8583) projected
  line L162 (15.9364, 57.8583) -> (13.5219, 58.4697) projected
  line L163 (13.5219, 58.4697) -> (11.6978, 55.7868) projected
  line L164 (11.6978, 55.7868) -> (10.9282, 52.1166) projected
  arc A86 (10.9282, 52.1166) -> (6.5861, 52.8411) centre (0, 0) ccw projected
  line L165 (6.5861, 52.8411) -> (7.05, 56.5623) projected
  line L166 (7.05, 56.5623) -> (6.1959, 59.6922) projected
  line L167 (6.1959, 59.6922) -> (3.7136, 59.8979) projected
  line L168 (3.7136, 59.8979) -> (2.356, 56.9513) projected
  line L169 (2.356, 56.9513) -> (2.201, 53.2045) projected
  arc A87 (2.201, 53.2045) -> (-2.201, 53.2045) centre (0, 0) ccw projected
  line L170 (-2.201, 53.2045) -> (-2.356, 56.9513) projected
  line L171 (-2.356, 56.9513) -> (-3.7136, 59.8979) projected
  line L172 (-3.7136, 59.8979) -> (-6.1959, 59.6922) projected
  line L173 (-6.1959, 59.6922) -> (-7.05, 56.5623) projected
  line L174 (-7.05, 56.5623) -> (-6.5861, 52.8411) projected
  arc A88 (-6.5861, 52.8411) -> (-10.9282, 52.1166) centre (0, 0) ccw projected
  line L175 (-10.9282, 52.1166) -> (-11.6978, 55.7868) projected
  line L176 (-11.6978, 55.7868) -> (-13.5219, 58.4697) projected
  line L177 (-13.5219, 58.4697) -> (-15.9364, 57.8583) projected
  line L178 (-15.9364, 57.8583) -> (-16.2637, 54.6305) projected
  line L179 (-16.2637, 54.6305) -> (-15.1937, 51.0364) projected
  arc A89 (-15.1937, 51.0364) -> (-19.3573, 49.607) centre (0, 0) ccw projected
  line L180 (-19.3573, 49.607) -> (-20.7204, 53.1005) projected
  line L181 (-20.7204, 53.1005) -> (-22.9612, 55.4467) projected
  line L182 (-22.9612, 55.4467) -> (-25.2422, 54.4461) projected
  line L183 (-25.2422, 54.4461) -> (-25.0337, 51.2085) projected
  line L184 (-25.0337, 51.2085) -> (-23.3868, 47.8395) projected
  arc A90 (-23.3868, 47.8395) -> (-27.2583, 45.7444) centre (0, 0) ccw projected
  line L185 (-27.2583, 45.7444) -> (-29.1779, 48.9658) projected
  line L186 (-29.1779, 48.9658) -> (-31.7743, 50.9111) projected
  line L187 (-31.7743, 50.9111) -> (-33.8595, 49.5488) projected
  line L188 (-33.8595, 49.5488) -> (-33.121, 46.3897) projected
  line L189 (-33.121, 46.3897) -> (-30.9419, 43.3377) projected
  arc A91 (-30.9419, 43.3377) -> (-34.4158, 40.6339) centre (0, 0) ccw projected
  line L190 (-34.4158, 40.6339) -> (-36.8395, 43.4955) projected
  line L191 (-36.8395, 43.4955) -> (-39.7206, 44.9869) projected
  line L192 (-39.7206, 44.9869) -> (-41.5531, 43.3) projected
  line L193 (-41.5531, 43.3) -> (-40.3047, 40.3055) projected
  line L194 (-40.3047, 40.3055) -> (-37.6531, 37.6538) projected
  arc A92 (-37.6531, 37.6538) -> (-40.6345, 34.4151) centre (0, 0) ccw projected
  line L195 (-40.6345, 34.4151) -> (-43.4961, 36.8387) projected
  line L196 (-43.4961, 36.8387) -> (-46.5835, 37.8355) projected
  line L197 (-46.5835, 37.8355) -> (-48.1134, 35.87) projected
  line L198 (-48.1134, 35.87) -> (-46.3891, 33.1218) projected
  line L199 (-46.3891, 33.1218) -> (-43.3372, 30.9427) projected
  arc A93 (-43.3372, 30.9427) -> (-45.7449, 27.2575) centre (0, 0) ccw projected
  line L200 (-45.7449, 27.2575) -> (-48.9663, 29.177) projected
  line L201 (-48.9663, 29.177) -> (-52.1757, 29.6521) projected
  line L202 (-52.1757, 29.6521) -> (-53.3612, 27.4616) projected
  line L203 (-53.3612, 27.4616) -> (-51.2081, 25.0347) projected
  line L204 (-51.2081, 25.0347) -> (-47.8391, 23.3877) projected
  arc A94 (-47.8391, 23.3877) -> (-49.6074, 19.3563) centre (0, 0) ccw projected
  line L205 (-49.6074, 19.3563) -> (-53.1009, 20.7195) projected
  line L206 (-53.1009, 20.7195) -> (-56.3447, 20.6599) projected
  line L207 (-56.3447, 20.6599) -> (-57.1534, 18.3041) projected
  line L208 (-57.1534, 18.3041) -> (-54.6302, 16.2647) projected
  line L209 (-54.6302, 16.2647) -> (-51.0361, 15.1946) projected
  arc A95 (-51.0361, 15.1946) -> (-52.1168, 10.9272) centre (0, 0) ccw projected
  line L210 (-52.1168, 10.9272) -> (-55.787, 11.6968) projected
  line L211 (-55.787, 11.6968) -> (-58.9767, 11.1041) projected
  line L212 (-58.9767, 11.1041) -> (-59.3867, 8.6473) projected
  line L213 (-59.3867, 8.6473) -> (-56.5622, 7.051) projected
  line L214 (-56.5622, 7.051) -> (-52.841, 6.5871) projected
  arc A96 (-52.841, 6.5871) -> (-53.2045, 2.2001) centre (0, 0) ccw projected
  line L215 (-53.2045, 2.2001) -> (-56.9513, 2.355) projected
  line L216 (-56.9513, 2.355) -> (-60, 1.2454) projected
  line L217 (-60, 1.2454) -> (-60, -1.2454) projected
  line L218 (-60, -1.2454) -> (-56.9513, -2.355) projected
  line L219 (-56.9513, -2.355) -> (-53.2045, -2.2001) projected
  arc A97 (-53.2045, -2.2001) -> (-52.841, -6.5871) centre (0, 0) ccw projected
  circle A98 centre (0, 0) radius 7 projected
  circle A99 centre (0, 0) radius 4
  dimension "d42" = 8
  constraints: 1 centre point, 1 coincident
  measures "d42" diameter of A99
extrude "押し出し5" add sketch "スケッチ5" against normal up to surface (5.5 mm away) contours A98
equation "\"BendRadius\" = Thickness"
equation "\"BendReliefWidth\" = Thickness"
equation "\"BendReliefDepth\" = 0.5 * Thickness"
equation "\"CornerReliefSize\" = 4 * Thickness"
equation "\"MinimumRemnant\" = 2 * Thickness"
equation "\"TransitionRadius\" = BendRadius"
equation "\"JacobiRadiusSize\" = BendRadius"
equation "\"GapSize\" = Thickness"
equation "\"Thickness\" = 3.048"
